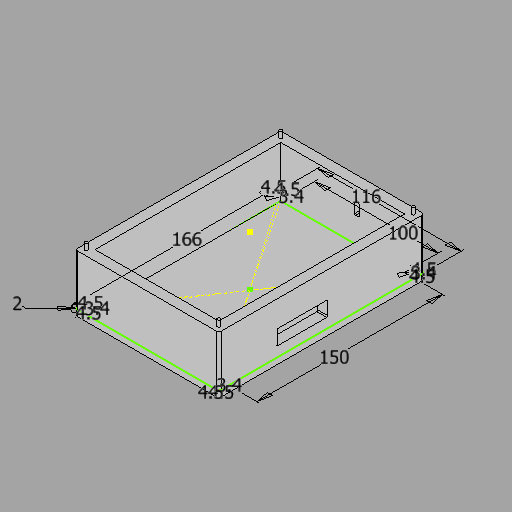
# Autodesk Inventor part: IN_FRONT_Bottom
Saved by Autodesk Inventor 2027 (Build 310192000, 192)
## iProperties
Created: 2026-11-12
Part Number: IN_FRONT_Bottom
Material: Generic
Document SubType Name: Modeling
Designer: jyjhm
Density: 1 g/cm^3
Appearance: Default
Author: jyjhm
Autodesk Inventor part; units mm, degrees
ref_plane "YZ Plane" through (0, 0, 0) normal (1, 0, 0) x (0, 1, 0)
ref_plane "XZ Plane" through (0, 0, 0) normal (0, 1, 0) x (-1, 0, 0)
ref_plane "XY Plane" through (0, 0, 0) normal (0, 0, 1) x (1, 0, 0)
sketch "Sketch1" plane through (0, 0, 0) normal (0, 1, 0) x (-1, 0, 0)
  line L0 (-56, -83) -> (56, -83)
  line L1 (58, -81) -> (58, 81)
  line L2 (56, 83) -> (-56, 83)
  line L3 (-58, 81) -> (-58, -81)
  line L4 (-58, -83) -> (58, 83) construction
  line L5 (58, -83) -> (-58, 83) construction
  line L6 (-50, -75) -> (50, -75)
  line L7 (50, -75) -> (50, 75)
  line L8 (50, 75) -> (-50, 75)
  line L9 (-50, 75) -> (-50, -75)
  line L10 (-50, -75) -> (50, 75) construction
  line L11 (50, -75) -> (-50, 75) construction
  arc A0 (58, 81) -> (56, 83) centre (56, 81) ccw
  arc A1 (56, -83) -> (58, -81) centre (56, -81) ccw
  arc A2 (-58, -81) -> (-56, -83) centre (-56, -81) ccw
  arc A3 (-56, 83) -> (-58, 81) centre (-56, 81) ccw
  circle A4 centre (-53.5, 78.5) radius 1.7
  circle A5 centre (53.5, 78.5) radius 1.7
  circle A6 centre (53.5, -78.5) radius 1.7
  circle A7 centre (-53.5, -78.5) radius 1.7
  point P0 (0, 0)
  point P1 (0, 0)
  dimension "d0" = 166
  dimension "d2" = 116
  dimension "d4" = 150
  dimension "d5" = 100
  dimension "d6" = 2
  dimension "d7" = 3.4
  dimension "d8" = 4.5
  dimension "d9" = 4.5
  dimension "d10" = 3.4
  dimension "d11" = 4.5
  dimension "d12" = 4.5
  dimension "d13" = 3.4
  dimension "d14" = 3.4
  dimension "d15" = 4.5
  dimension "d16" = 4.5
  dimension "d17" = 4.5
  dimension "d18" = 4.5
  constraints: 24 end point, 8 centre point, 8 point on circle, 8 point on line, 8 tangent, 4 midpoint, 4 parallel, 3 equal radius, 2 horizontal, 2 perpendicular
  measures "d0" distance of L5.start L4.end
  measures "d2" distance of L4.start L5.start
  measures "d4" distance of L8.end L6.start
  measures "d5" distance of L6.start L6.end
  measures "d6" radius of A0
  measures "d7" diameter of A4
  measures "d8" distance from line of L3 A4.centre
  measures "d9" distance from line of L2 A4.centre
  measures "d10" diameter of A5
  measures "d11" distance from line of L1 A5.centre
  measures "d12" distance from line of L2 A5.centre
  measures "d13" diameter of A6
  measures "d14" diameter of A7
  measures "d15" distance from line of L1 A6.centre
  measures "d16" distance from line of L0 A6.centre
  measures "d17" distance from line of L3 A7.centre
  measures "d18" distance from line of A7.centre L0
extrude "Extrusion1" add sketch "Sketch1" against normal blind 5 contours A2 L3 A3 L2 A0 L1 A1 L0 | L9 L8 L7 L6 | A4 | A5 | A6 | A7
extrude "Extrusion2" add sketch "Sketch1" along normal blind 41 contours A2 L3 A3 L2 A0 L1 A1 L0 | A4 | A5 | A6 | A7
sketch "Sketch2" plane through (58, -5, 81) normal (1, 0, 0) x (0, 0, -1)
  line L0 (85.2, 13) -> (45.8, 13)
  line L1 (45, 13.8) -> (45, 24.2)
  line L2 (45.8, 25) -> (85.2, 25)
  line L3 (86, 24.2) -> (86, 13.8)
  line L4 (86, 13) -> (45, 25) construction
  line L5 (45, 13) -> (86, 25) construction
  line L6 (0, 0) -> (0, 46) projected
  line L7 (162, 0) -> (0, 0) projected
  arc A0 (45.8, 25) -> (45, 24.2) centre (45.8, 24.2) ccw
  arc A1 (45, 13.8) -> (45.8, 13) centre (45.8, 13.8) ccw
  arc A2 (86, 24.2) -> (85.2, 25) centre (85.2, 24.2) ccw
  arc A3 (85.2, 13) -> (86, 13.8) centre (85.2, 13.8) ccw
  point P0 (81, 5)
  point P1 (65.5, 19)
  point P2 (0, 23)
  point P3 (65.5, 25)
  dimension "d23" = 45
  dimension "d24" = 41
  dimension "d25" = 25
  dimension "d26" = 12
  dimension "d27" = 0.8
  constraints: 12 end point, 8 point on circle, 8 point on line, 8 tangent, 4 centre point, 4 midpoint, 3 equal radius, 2 parallel, 1 horizontal, 1 perpendicular
  measures "d23" distance from line of point (0, 23) L1
  measures "d24" distance of L4.start L5.start
  measures "d25" distance from line of L7 point (65.5, 25)
  measures "d26" distance of L5.end L4.start
  measures "d27" radius of A0
extrude "Extrusion3" cut sketch "Sketch2" against normal blind 8
sketch "Sketch3" plane through (56, -5, -83) normal (0, 0, -1) x (-1, 0, 0)
  line L0 (43.3, 34.7) -> (45.5, 34.7)
  line L1 (46.3, 33.9) -> (46.3, 26.1)
  line L2 (45.5, 25.3) -> (43.3, 25.3)
  line L3 (42.5, 26.1) -> (42.5, 33.9)
  line L4 (42.5, 34.7) -> (46.3, 25.3) construction
  line L5 (46.3, 34.7) -> (42.5, 25.3) construction
  line L6 (6, 5) -> (106, 5) projected
  line L7 (0, 0) -> (0, 46) projected
  arc A0 (43.3, 34.7) -> (42.5, 33.9) centre (43.3, 33.9) ccw
  arc A1 (46.3, 33.9) -> (45.5, 34.7) centre (45.5, 33.9) ccw
  arc A2 (45.5, 25.3) -> (46.3, 26.1) centre (45.5, 26.1) ccw
  arc A3 (42.5, 26.1) -> (43.3, 25.3) centre (43.3, 26.1) ccw
  point P0 (56, 5)
  point P1 (44.4, 30)
  dimension "d30" = 25
  dimension "d31" = 44.4
  dimension "d32" = 9.4
  dimension "d33" = 3.8
  dimension "d34" = 0.8
  constraints: 12 end point, 8 point on circle, 8 point on line, 8 tangent, 4 centre point, 3 equal radius, 2 midpoint, 2 parallel, 1 horizontal, 1 perpendicular
  measures "d30" distance from line of L6 point (44.4, 30)
  measures "d31" distance from line of L7 point (44.4, 30)
  measures "d32" distance of L5.start L4.end
  measures "d33" distance of L4.end L5.end
  measures "d34" radius of A0
extrude "Extrusion4" cut sketch "Sketch3" against normal blind 8
sketch "Sketch4" plane through (0, 41, 0) normal (0, 1, 0) x (1, 0, 0)
  point P0 (0, 0)
sketch "Sketch5" plane through (0, 41, 0) normal (0, 1, 0) x (1, 0, 0)
  circle A0 centre (-53.5, 78.5) radius 1.7 projected
  circle A1 centre (-53.5, -78.5) radius 1.7 projected
  arc A2 (-56, 83) -> (-58, 81) centre (-56, 81) ccw projected
  line L0 (-58, 81) -> (-58, -81) projected
  arc A3 (-58, -81) -> (-56, -83) centre (-56, -81) ccw projected
  line L1 (-56, -83) -> (56, -83) projected
  arc A4 (56, -83) -> (58, -81) centre (56, -81) ccw projected
  line L2 (58, -81) -> (58, 81) projected
  arc A5 (58, 81) -> (56, 83) centre (56, 81) ccw projected
  line L3 (56, 83) -> (-56, 83) projected
  line L4 (50, 75) -> (50, -75) projected
  line L5 (50, -75) -> (-50, -75) projected
  line L6 (-50, -75) -> (-50, 75) projected
  line L7 (-50, 75) -> (50, 75) projected
  circle A6 centre (53.5, -78.5) radius 1.7 projected
  circle A7 centre (53.5, 78.5) radius 1.7 projected
  circle A8 centre (-53.5, -78.5) radius 1.2
  circle A9 centre (53.5, -78.5) radius 1.2
  circle A10 centre (53.5, 78.5) radius 1.2
  circle A11 centre (-53.5, 78.5) radius 1.2
  point P0 (0, 0)
  dimension "d37" = 0.5
  dimension "d38" = 0.5
  dimension "d39" = 0.5
  dimension "d40" = 0.5
  constraints: 4 centre point, 4 coincident
  measures "d37" radial gap between concentric circles of A1 A8
  measures "d38" radial gap between concentric circles of A6 A9
  measures "d39" radial gap between concentric circles of A7 A10
  measures "d40" radial gap between concentric circles of A0 A11
extrude "Extrusion5" add sketch "Sketch5" along normal blind 5 contours A8 | A9 | A10 | A11
body "Solid1"
